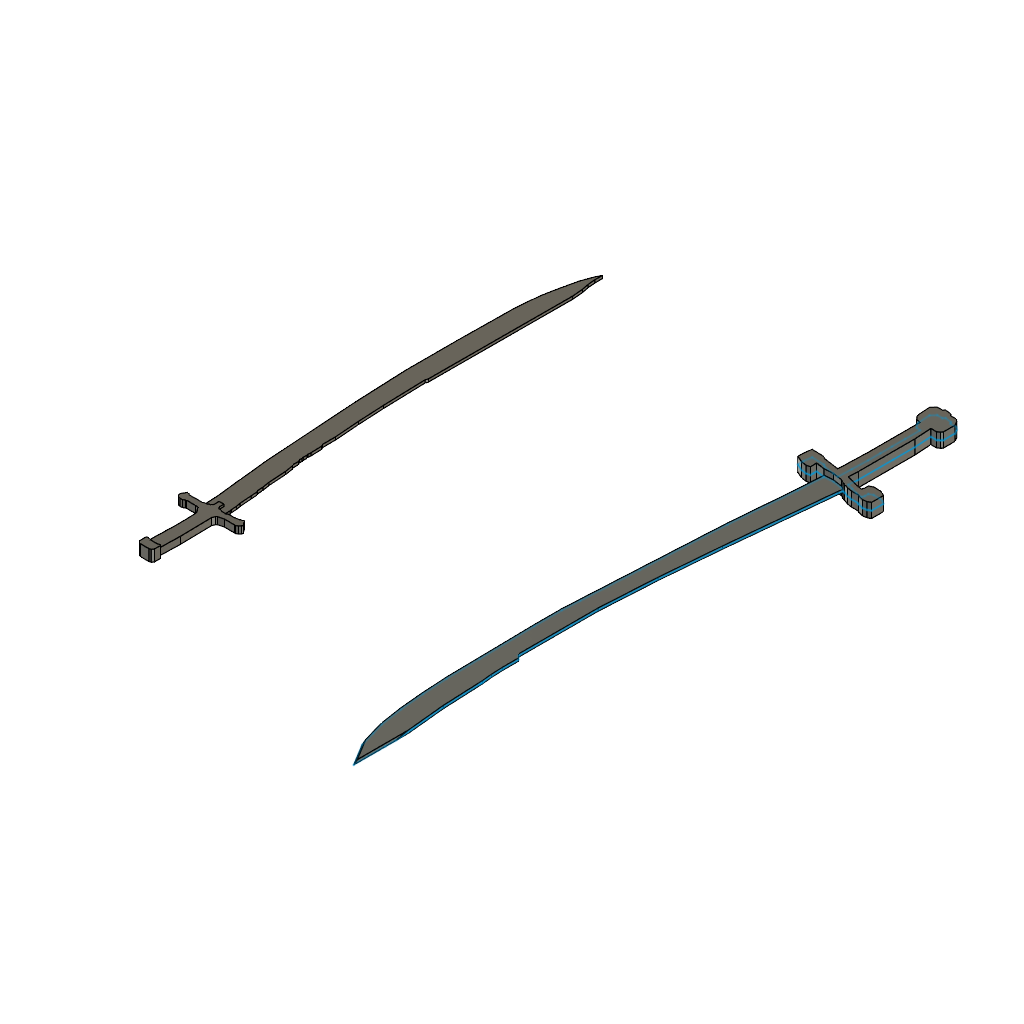
Hungarian_Saber_and_Early_Ottoman_Kilij (Autodesk Fusion 360 design; units mm, degrees)
part number: 2026-09-20-18-35-14-344
Autodesk Fusion 360 part; units mm, degrees
sketch "Sketch1" plane through (0, 0, 0) normal (0, 0, 1) x (1, 0, 0)
sketch "Sketch2" plane through (0, 0, 0) normal (0, 0, 1) x (1, 0, 0)
sketch "Sketch3" plane through (0, 0, 0) normal (0, 0, 1) x (1, 0, 0)
  line L0 (20.535, 40.8255) -> (20.535, 39.7757)
  line L1 (20.535, 39.7757) -> (20.535, 38.8297)
  line L2 (20.535, 38.8297) -> (20.535, 38)
  line L3 (20.535, 38) -> (20.535, 37.125)
  line L4 (20.535, 37.125) -> (20.5, 36)
  line L5 (20.5, 36) -> (20.4699, 35.0318)
  line L6 (20.535, 40.8255) -> (20.25, 40.875)
  line L7 (20.25, 40.875) -> (20.059, 41.0864)
  line L8 (20.059, 41.0864) -> (20, 41.25)
  line L9 (20, 41.25) -> (19.9441, 42.0918)
  line L10 (19.9441, 42.0918) -> (20.2027, 42.3838)
  line L11 (20.2027, 42.3838) -> (20.5761, 42.3838)
  line L12 (21.2093, 42.3262) -> (21.625, 42.3262)
  line L13 (21.625, 42.3262) -> (21.7909, 42.195)
  line L14 (21.7909, 42.195) -> (21.9608, 41.8938)
  line L15 (21.9608, 41.8938) -> (21.9608, 41.0647)
  line L16 (21.9608, 41.0647) -> (21.8758, 40.9573)
  line L17 (21.8758, 40.9573) -> (21.7103, 40.8321)
  line L18 (21.7103, 40.8321) -> (21.2988, 40.8321)
  line L19 (20.5761, 42.3838) -> (20.6845, 42.5021)
  line L20 (20.6845, 42.5021) -> (21.1318, 42.443)
  line L21 (21.1318, 42.443) -> (21.2093, 42.3262)
  line L22 (21.2988, 40.8321) -> (21.375, 39.625)
  line L23 (21.375, 39.625) -> (21.375, 38.0611)
  line L24 (21.375, 38.0611) -> (21.375, 35.5802)
  line L25 (21.375, 35.5802) -> (21.3369, 34.91)
  line L26 (21.3369, 34.91) -> (21.7185, 34.8114)
  line L27 (21.7185, 34.8114) -> (22.125, 34.6875)
  line L28 (22.125, 34.6875) -> (22.5625, 34.625)
  line L29 (22.5625, 34.625) -> (22.6193, 34.8114)
  line L30 (22.6193, 34.8114) -> (22.6193, 35.0625)
  line L31 (22.6193, 35.0625) -> (22.875, 35.1875)
  line L32 (22.875, 35.1875) -> (23.3125, 35.1875)
  line L33 (23.3125, 35.1875) -> (23.5625, 35.125)
  line L34 (23.5625, 35.125) -> (23.75, 35)
  line L35 (23.75, 35) -> (23.75, 34.1588)
  line L36 (23.75, 34.1588) -> (23.5346, 34.0415)
  line L37 (23.5346, 34.0415) -> (23.25, 34)
  line L38 (23.25, 34) -> (22.8707, 34.1002)
  line L39 (22.8707, 34.1002) -> (22.8641, 34.1456)
  line L40 (22.8641, 34.1456) -> (22.3149, 34.1456)
  line L41 (22.3149, 34.1456) -> (21.9876, 34.199)
  line L42 (21.9876, 34.199) -> (21.6695, 34.3194)
  line L43 (21.6695, 34.3194) -> (21.5277, 34.3425)
  line L44 (20.4699, 35.0318) -> (20.1137, 35.0824)
  line L45 (20.1137, 35.0824) -> (19.3962, 35.1842)
  line L46 (19.3962, 35.1842) -> (19.2212, 35.2941)
  line L47 (19.2212, 35.2941) -> (18.3538, 35.3211)
  line L48 (18.3538, 35.3211) -> (18.276, 34.7731)
  line L49 (18.276, 34.7731) -> (18.276, 34.375)
  line L50 (18.276, 34.375) -> (18.7493, 34.1717)
  line L51 (18.7493, 34.1717) -> (19.1165, 34.1196)
  line L52 (19.1165, 34.1196) -> (19.3695, 34.1717)
  line L53 (19.3695, 34.1717) -> (19.3695, 34.375)
  line L54 (19.3695, 34.375) -> (19.3695, 34.625)
  line L55 (19.3695, 34.625) -> (19.9776, 34.5378)
  line L56 (19.9776, 34.5378) -> (19.9776, 34.4491)
  line L57 (19.9776, 34.4491) -> (19.875, 32.75)
  line L58 (19.875, 32.75) -> (19.4846, 28.1583)
  line L59 (19.4846, 28.1583) -> (19.1588, 22.2317)
  line L60 (19.1588, 22.2317) -> (18.9379, 18.2118)
  line L61 (21.5277, 34.3425) -> (21.4775, 34.0352)
  line L62 (21.4775, 34.0352) -> (21.125, 30.5)
  line L63 (21.125, 30.5) -> (20.9643, 28.8881)
  line L64 (20.9643, 28.8881) -> (20.7301, 26.5399)
  line L65 (20.7301, 26.5399) -> (20.5, 23.875)
  line L66 (20.5, 23.875) -> (20.3652, 22.3135)
  line L67 (20.3652, 22.3135) -> (20.25, 20.375)
  line L68 (20.25, 20.375) -> (20.1261, 18.2898)
  line L69 (20.1261, 18.2898) -> (20.1261, 16.375)
  line L70 (20.1261, 16.375) -> (20.1261, 12.625)
  line L71 (20.1261, 12.625) -> (20.375, 12.375)
  line L72 (20.375, 12.375) -> (20.375, 11.25)
  line L73 (18.9379, 18.2118) -> (18.8692, 16.9629)
  line L74 (18.8692, 16.9629) -> (18.8692, 15)
  line L75 (18.8692, 15) -> (18.9379, 11.0327)
  line L76 (18.9379, 11.0327) -> (18.9793, 8.6387)
  line L77 (18.9793, 8.6387) -> (19.0903, 6.8371)
  line L78 (19.0903, 6.8371) -> (19.25, 5.125)
  line L79 (19.25, 5.125) -> (19.5, 3.5)
  line L80 (19.5, 3.5) -> (19.75, 2.625)
  line L81 (19.75, 2.625) -> (20.06, 1.54)
  line L82 (20.06, 1.54) -> (21, 0)
  line L83 (21, 0) -> (21, 2.25)
  line L84 (21, 2.25) -> (21, 3)
  line L85 (21, 3) -> (20.875, 4.25)
  line L86 (20.875, 4.25) -> (20.7563, 5.4372)
  line L87 (20.7563, 5.4372) -> (20.625, 6.75)
  line L88 (20.625, 6.75) -> (20.5511, 8.3332)
  line L89 (20.5511, 8.3332) -> (20.4873, 9.7001)
  line L90 (20.4873, 9.7001) -> (20.4973, 9.4847)
  line L91 (20.375, 11.25) -> (20.4152, 10.4002)
  line L92 (20.4152, 10.4002) -> (20.4873, 9.7001)
  line L93 (19.9776, 34.5378) -> (20.6065, 34.5814)
  line L94 (20.6065, 34.5814) -> (21.2828, 34.4844)
  line L95 (21.2828, 34.4844) -> (21.5277, 34.3425)
  constraint vertical L0
  constraint parallel L0 L1
  constraint parallel L1 L2
  constraint parallel L2 L3
  constraint parallel L4 L5
  constraint horizontal L11
  constraint horizontal L12
  constraint perpendicular L12 L15
  constraint perpendicular L13 L16
  constraint perpendicular L15 L18
  constraint perpendicular L18 L23
  constraint perpendicular L18 L24
  constraint perpendicular L27 L29
  constraint vertical L30
  constraint horizontal L32
  constraint perpendicular L32 L35
  constraint perpendicular L37 L39
  constraint horizontal L40
  constraint parallel L41 L43
  constraint parallel L44 L45
  constraint perpendicular L5 L47
  constraint perpendicular L44 L48
  constraint vertical L49
  constraint perpendicular L48 L51
  constraint vertical L53
  constraint parallel L53 L54
  constraint vertical L56
  constraint parallel L59 L60
  constraint perpendicular L43 L61
  constraint parallel L62 L63
  constraint parallel L63 L64
  constraint parallel L65 L66
  constraint parallel L67 L68
  constraint vertical L69
  constraint parallel L69 L70
  constraint parallel L70 L72
  constraint parallel L60 L73
  constraint parallel L69 L74
  constraint parallel L75 L76
  constraint parallel L80 L81
  constraint vertical L83
  constraint parallel L83 L84
  constraint parallel L85 L86
  constraint parallel L86 L87
  constraint parallel L88 L89
  constraint coincident L89 L90.end
  constraint parallel L55 L94
extrude "Extrude9" add sketch "Sketch3" along normal mid plane 0.2 contours L56 L57 L58 L59 L60 L61 L62 L63 L64 L65 L66 L67 L68 L69 L70 L71 L72 L73 L74 L75 L76 L77 L78 L79 L80 L81 L82 L83 L84 L85 L86 L87 L88 L89 L90 L91 L92 L93 L94 L95 makes body 1
extrude "Extrude10" add sketch "Sketch3" along normal mid plane 1 separate body contours L0 L1 L2 L3 L4 L5 L6 L7 L8 L9 L10 L11 L12 L13 L14 L15 L16 L17 L18 L19 L20 L21 L22 L23 L24 L25 L26 L27 L28 L29 L30 L31 L32 L33 L34 L35 L36 L37 L38 L39 L40 L41 L42 L43 L44 L45 L46 L47 L48 L49 L50 L51 L52 L53 L54 L55 L93 L94 L95 makes body 2
chamfer "Chamfer5" distance 0.1 angle 45 1 edges at (20.53, 0.77, 0.1) tangent chain off on bodies 1
chamfer "Chamfer6" distance 0.1 angle 45 1 edges at (21, 1.596, 0.1) tangent chain off on bodies 1
chamfer "Chamfer7" distance 0.1 angle 45 1 edges at (20.53, 0.77, -0.1) tangent chain off on bodies 1
chamfer "Chamfer8" distance 0.1 angle 45 1 edges at (21, 1.596, -0.1) tangent chain off on bodies 1
sketch "Sketch4" plane through (0, 0, 0) normal (0, 0, 1) x (1, 0, 0)
sketch "Sketch5" plane through (0, 0, 0) normal (0, 0, 1) x (1, 0, 0)
  line L0 (0.9998, 10.1385) -> (0.9211, 9.9479)
  line L1 (0.9211, 9.9479) -> (0.9412, 8.882)
  line L2 (0.9412, 8.882) -> (0.964, 7.6796)
  line L3 (0.964, 7.6796) -> (0.9526, 7.2039)
  line L4 (0.9526, 7.2039) -> (0.9314, 6.3174)
  line L5 (0.9314, 6.3174) -> (0.7833, 6.2509)
  line L6 (0.7833, 6.2509) -> (0.5428, 6.2464)
  line L7 (0.5428, 6.2464) -> (0.2434, 6.2509)
  line L8 (0.2434, 6.2509) -> (0.0858, 6.3049)
  line L9 (0.0858, 6.3049) -> (0.07, 6.34)
  line L10 (0.07, 6.34) -> (0.1, 7.5)
  line L11 (0.1, 7.5) -> (0.118, 8.2452)
  line L12 (0.118, 8.2452) -> (0.1, 7.5)
  line L13 (0.118, 8.2452) -> (0.109, 8.9555)
  line L14 (0.109, 8.9555) -> (0.0862, 9.6131)
  line L15 (0.0862, 9.6131) -> (0.0385, 9.7795)
  line L16 (0.0385, 9.7795) -> (-0.05, 9.9)
  line L17 (-0.05, 9.9) -> (-0.1552, 10.0432)
  line L18 (-0.1552, 10.0432) -> (-0.1742, 10.1095)
  line L19 (-0.1742, 10.1095) -> (-0.3662, 10.1243)
  line L20 (-0.3662, 10.1243) -> (-0.4152, 10.128)
  line L21 (-0.4152, 10.128) -> (-1.0257, 10.1243)
  line L22 (-1.0257, 10.1243) -> (-0.4152, 10.128)
  line L23 (-1.0257, 10.1243) -> (-1.1064, 10.1012)
  line L24 (-1.1064, 10.1012) -> (-1.2276, 10.019)
  line L25 (-1.2276, 10.019) -> (-1.4058, 10.0179)
  line L26 (-1.4058, 10.0179) -> (-1.5371, 10.0484)
  line L27 (-1.5371, 10.0484) -> (-1.6602, 10.1906)
  line L28 (-1.6602, 10.1906) -> (-1.6895, 10.3049)
  line L29 (-1.6895, 10.3049) -> (-1.6602, 10.3698)
  line L30 (-1.6602, 10.3698) -> (-1.6513, 10.3896)
  line L31 (-1.6513, 10.3896) -> (-1.6181, 10.4631)
  line L32 (-1.6181, 10.4631) -> (-1.5768, 10.4846)
  line L33 (-1.5768, 10.4846) -> (-1.56, 10.54)
  line L34 (-1.56, 10.54) -> (-1.56, 10.58)
  line L35 (-1.56, 10.58) -> (-1.54, 10.61)
  line L36 (-1.54, 10.61) -> (-1.5186, 10.6444)
  line L37 (-1.5186, 10.6444) -> (-1.4309, 10.6444)
  line L38 (-1.4309, 10.6444) -> (-1.3487, 10.6195)
  line L39 (-1.3487, 10.6195) -> (-1.3, 10.57)
  line L40 (-1.3, 10.57) -> (-1.2734, 10.562)
  line L41 (-1.2734, 10.562) -> (-0.3379, 10.57)
  line L42 (-0.3379, 10.57) -> (-0.2951, 10.6121)
  line L43 (-0.2951, 10.6121) -> (-0.0594, 10.6395)
  line L44 (0.9998, 10.1385) -> (1.0753, 10.2152)
  line L45 (1.0753, 10.2152) -> (1.4, 10.3)
  line L46 (1.4, 10.3) -> (1.4603, 10.3158)
  line L47 (1.4603, 10.3158) -> (1.9, 10.3158)
  line L48 (1.9, 10.3158) -> (2.1, 10.3158)
  line L49 (2.1, 10.3158) -> (2.2, 10.3158)
  line L50 (2.2, 10.3158) -> (2.2647, 10.3079)
  line L51 (2.2647, 10.3079) -> (2.3879, 10.3893)
  line L52 (2.3879, 10.3893) -> (2.5, 10.5)
  line L53 (2.5, 10.5) -> (2.5461, 10.6141)
  line L54 (2.5461, 10.6141) -> (2.444, 10.7175)
  line L55 (2.444, 10.7175) -> (2.3731, 10.8046)
  line L56 (2.3731, 10.8046) -> (2.35, 10.85)
  line L57 (2.35, 10.85) -> (2.3414, 10.8862)
  line L58 (2.3414, 10.8862) -> (2.3171, 10.9146)
  line L59 (2.3171, 10.9146) -> (2.28, 10.93)
  line L60 (2.28, 10.93) -> (2.2251, 10.9223)
  line L61 (2.2251, 10.9223) -> (2.2058, 10.9004)
  line L62 (2.2058, 10.9004) -> (2.1809, 10.8722)
  line L63 (2.1809, 10.8722) -> (2.1558, 10.8686)
  line L64 (2.1558, 10.8686) -> (2.1163, 10.8631)
  line L65 (2.1163, 10.8631) -> (2.08, 10.8631)
  line L66 (2.08, 10.8631) -> (2.06, 10.85)
  line L67 (2.06, 10.85) -> (2.05, 10.83)
  line L68 (2.05, 10.83) -> (2.04, 10.81)
  line L69 (2.04, 10.81) -> (1.9855, 10.81)
  line L70 (1.9855, 10.81) -> (1.936, 10.81)
  line L71 (1.936, 10.81) -> (1.88, 10.8)
  line L72 (1.88, 10.8) -> (1.82, 10.8)
  line L73 (1.82, 10.8) -> (1.7858, 10.7832)
  line L74 (1.7858, 10.7832) -> (1.7402, 10.7607)
  line L75 (1.7402, 10.7607) -> (1.4783, 10.7607)
  line L76 (1.4783, 10.7607) -> (1.364, 10.7607)
  line L77 (1.364, 10.7607) -> (1.28, 10.74)
  line L78 (1.28, 10.74) -> (1.25, 10.71)
  line L79 (1.25, 10.71) -> (1.22, 10.69)
  line L80 (1.22, 10.69) -> (1.1339, 10.69)
  line L81 (1.1339, 10.69) -> (1.02, 10.69)
  line L82 (1.02, 10.69) -> (0.91, 10.7)
  line L83 (0.91, 10.7) -> (0.86, 10.73)
  line L84 (0.86, 10.73) -> (0.82, 10.76)
  line L85 (0.82, 10.76) -> (0.7495, 10.7664)
  line L86 (0.7495, 10.7664) -> (0.82, 10.76)
  line L87 (0.65, 10.76) -> (0.5811, 10.8117)
  line L88 (0.5811, 10.8117) -> (0.53, 10.88)
  line L89 (0.65, 10.76) -> (0.7495, 10.7664)
  line L90 (-0.0594, 10.6395) -> (0, 10.7)
  line L91 (0, 10.7) -> (0.1019, 10.7119)
  line L92 (0.1019, 10.7119) -> (0.15, 10.8)
  line L93 (0.15, 10.8) -> (0.1912, 10.8419)
  line L94 (0.1912, 10.8419) -> (0.1912, 11.0201)
  line L95 (0.1912, 11.0201) -> (0.1912, 11.2204)
  line L96 (0.1912, 11.2204) -> (0.53, 11.2204)
  line L97 (0.53, 11.2204) -> (0.53, 10.88)
  line L98 (0.9314, 6.3174) -> (0.9739, 6.2635)
  line L99 (0.9739, 6.2635) -> (0.9739, 5.828)
  line L100 (0.9739, 5.828) -> (0.8774, 5.6877)
  line L101 (0.8774, 5.6877) -> (0.7541, 5.6494)
  line L102 (0.7541, 5.6494) -> (0.1674, 5.6494)
  line L103 (0.1674, 5.6494) -> (0.0101, 5.7196)
  line L104 (0.0101, 5.7196) -> (-0.075, 5.828)
  line L105 (-0.075, 5.828) -> (-0.075, 6.2659)
  line L106 (-0.075, 6.2659) -> (-0.0325, 6.3082)
  line L107 (-0.0325, 6.3082) -> (0.03, 6.33)
  line L108 (0.03, 6.33) -> (0.07, 6.34)
  line L109 (-0.2951, 10.6121) -> (-0.3632, 11.7311)
  line L110 (-0.3632, 11.7311) -> (-0.5655, 13.4701)
  line L111 (-0.5655, 13.4701) -> (-0.572, 13.5768)
  line L112 (-0.572, 13.5768) -> (-0.6579, 14.4362)
  line L113 (-0.6579, 14.4362) -> (-0.7776, 15.4651)
  line L114 (-0.7776, 15.4651) -> (-0.8555, 16.6133)
  line L115 (-0.8555, 16.6133) -> (-0.9663, 18.2476)
  line L116 (-0.9663, 18.2476) -> (-1.164, 21.1632)
  line L117 (-1.164, 21.1632) -> (-1.2452, 22.3594)
  line L118 (-1.2452, 22.3594) -> (-1.3, 23.6)
  line L119 (-1.3, 23.6) -> (-1.3553, 24.8509)
  line L120 (-1.3553, 24.8509) -> (-1.4131, 26.1577)
  line L121 (-1.4131, 26.1577) -> (-1.4131, 27.7)
  line L122 (-1.4131, 27.7) -> (-1.4131, 29.8863)
  line L123 (-1.4131, 29.8863) -> (-1.3842, 32.1188)
  line L124 (-1.3842, 32.1188) -> (-1.363, 33.7541)
  line L125 (-1.363, 33.7541) -> (-1.3, 34.65)
  line L126 (-1.3, 34.65) -> (-1.1996, 35.549)
  line L127 (-1.1996, 35.549) -> (-1.0312, 36.4509)
  line L128 (-1.0312, 36.4509) -> (-0.7364, 37.7837)
  line L129 (-0.7364, 37.7837) -> (-0.4272, 38.6431)
  line L130 (-0.4272, 38.6431) -> (-0.2481, 38.9641)
  line L131 (-0.2481, 38.9641) -> (-0.2481, 38.4346)
  line L132 (-0.2481, 38.4346) -> (-0.2, 37.9)
  line L133 (-0.2, 37.9) -> (-0.1, 37.4)
  line L134 (-0.1, 37.4) -> (-0.0324, 36.6479)
  line L135 (-0.0324, 36.6479) -> (-0.0662, 26.3744)
  line L136 (-0.0662, 26.3744) -> (-0.1246, 26.212)
  line L137 (-0.1246, 26.212) -> (-0.0322, 23.1576)
  line L138 (-0.0322, 23.1576) -> (0.0658, 21.2837)
  line L139 (0.0658, 21.2837) -> (0.1843, 19.739)
  line L140 (0.1843, 19.739) -> (0.2015, 19.515)
  line L141 (0.2015, 19.515) -> (0.2079, 18.5656)
  line L142 (0.2079, 18.5656) -> (0.2843, 18.4354)
  line L143 (0.2843, 18.4354) -> (0.3081, 17.6479)
  line L144 (0.3081, 17.6479) -> (0.2962, 17.4446)
  line L145 (0.2962, 17.4446) -> (0.317, 17.3548)
  line L146 (0.317, 17.3548) -> (0.3081, 17.093)
  line L147 (0.3081, 17.093) -> (0.3341, 16.981)
  line L148 (0.3341, 16.981) -> (0.3277, 16.7926)
  line L149 (0.3277, 16.7926) -> (0.4047, 16.6756)
  line L150 (0.4047, 16.6756) -> (0.4047, 16.25)
  line L151 (0.4047, 16.25) -> (0.4611, 16.1645)
  line L152 (0.4611, 16.1645) -> (0.5167, 15.8253)
  line L153 (0.5167, 15.8253) -> (0.5526, 15.607)
  line L154 (0.5526, 15.607) -> (0.6, 14.9)
  line L155 (0.6, 14.9) -> (0.6393, 14.3148)
  line L156 (0.6393, 14.3148) -> (0.7228, 13.8059)
  line L157 (0.7228, 13.8059) -> (0.75, 13.4)
  line L158 (0.75, 13.4) -> (0.8033, 13.3152)
  line L159 (0.8033, 13.3152) -> (0.8341, 12.8581)
  line L160 (0.8341, 12.8581) -> (0.9, 12)
  line L161 (0.9, 12) -> (0.9555, 11.7114)
  line L162 (0.9555, 11.7114) -> (0.9863, 11.3105)
  line L163 (0.9863, 11.3105) -> (1.0109, 11.1826)
  line L164 (1.0109, 11.1826) -> (1.0227, 10.8366)
  line L165 (1.0227, 10.8366) -> (1.02, 10.69)
  constraint parallel L1 L2
  constraint parallel L3 L4
  constraint perpendicular L2 L6
  constraint perpendicular L5 L9
  constraint parallel L11 L12
  constraint parallel L16 L17
  constraint parallel L15 L18
  constraint parallel L19 L20
  constraint parallel L21 L22
  constraint perpendicular L18 L23
  constraint parallel L22 L25
  constraint parallel L30 L31
  constraint vertical L34
  constraint perpendicular L34 L37
  constraint perpendicular L33 L38
  constraint parallel L38 L40
  constraint perpendicular L39 L42
  constraint parallel L45 L46
  constraint horizontal L47
  constraint parallel L47 L48
  constraint parallel L48 L49
  constraint perpendicular L52 L54
  constraint parallel L61 L62
  constraint parallel L60 L63
  constraint parallel L60 L64
  constraint horizontal L65
  constraint parallel L67 L68
  constraint parallel L65 L69
  constraint parallel L69 L70
  constraint parallel L69 L72
  constraint parallel L73 L74
  constraint parallel L72 L75
  constraint parallel L75 L76
  constraint parallel L76 L80
  constraint parallel L80 L81
  constraint parallel L82 L85
  constraint parallel L85 L86
  constraint parallel L84 L87
  constraint parallel L43 L91
  constraint parallel L90 L93
  constraint vertical L94
  constraint parallel L94 L95
  constraint perpendicular L94 L96
  constraint perpendicular L96 L97
  constraint vertical L99
  constraint perpendicular L99 L102
  constraint perpendicular L102 L105
  constraint perpendicular L43 L110
  constraint parallel L109 L111
  constraint parallel L110 L113
  constraint parallel L114 L115
  constraint parallel L115 L116
  constraint parallel L116 L117
  constraint parallel L118 L119
  constraint parallel L119 L120
  constraint vertical L121
  constraint parallel L121 L122
  constraint parallel L123 L124
  constraint vertical L131
  constraint parallel L132 L134
  constraint parallel L129 L136
  constraint parallel L139 L140
  constraint parallel L137 L143
  constraint parallel L145 L147
  constraint parallel L146 L148
  constraint vertical L150
  constraint parallel L149 L151
  constraint parallel L152 L153
  constraint parallel L154 L155
  constraint parallel L153 L156
  constraint parallel L155 L157
  constraint parallel L160 L162
  constraint parallel L161 L163
extrude "Extrude11" add sketch "Sketch5" along normal mid plane 0.2 separate body contours L43 L82 L83 L84 L85 L86 L87 L88 L89 L90 L91 L92 L93 L94 L95 L96 L97 L109 L110 L111 L112 L113 L114 L115 L116 L117 L118 L119 L120 L121 L122 L123 L124 L125 L126 L127 L128 L129 L130 L131 L132 L133 L134 L135 L136 L137 L138 L139 L140 L141 L142 L143 L144 L145 L146 L147 L148 L149 L150 L151 L152 L153 L154 L155 L156 L157 L158 L159 L160 L161 L162 L163 L164 L165 makes body 3
extrude "Extrude12" add sketch "Sketch5" along normal mid plane 0.5 contours L0 L1 L2 L3 L4 L5 L6 L7 L8 L9 L10 L11 L12 L13 L14 L15 L16 L17 L18 L19 L20 L21 L22 L23 L24 L25 L26 L27 L28 L29 L30 L31 L32 L33 L34 L35 L36 L37 L38 L39 L40 L41 L42 L43 L44 L45 L46 L47 L48 L49 L50 L51 L52 L53 L54 L55 L56 L57 L58 L59 L60 L61 L62 L63 L64 L65 L66 L67 L68 L69 L70 L71 L72 L73 L74 L75 L76 L77 L78 L79 L80 L81 L82 L83 L84 L85 L86 L87 L88 L89 L90 L91 L92 L93 L94 L95 L96 L97 bodies 3
extrude "Extrude13" add sketch "Sketch5" along normal mid plane 0.8 contours L5 L6 L7 L8 L9 L98 L99 L100 L101 L102 L103 L104 L105 L106 L107 L108 bodies 3
sketch "Sketch19" plane through (0, 0, 0) normal (0, 0, 1) x (1, 0, 0)
sketch "Sketch20" plane through (0, 0, 0) normal (0, 1, 0) x (1, 0, 0)
  line L0 (-2.2, 0) -> (-3.6, 0)
  circle A0 centre (-2.9, 0) radius 0.7
  constraint midpoint L0 A0.centre
  constraint coincident L0.end A0
sketch "Sketch21" plane through (0, 0, 0) normal (0, 0, 1) x (1, 0, 0)
  line L0 (-3.9, 1.65) -> (-1.8, 1.65)
  line L1 (-1.8, 1.65) -> (-1.8, 0)
  line L2 (-1.8, 0) -> (-3.9, 0)
  line L3 (-3.9, 0) -> (-3.9, 1.65)
  constraint horizontal L0
  constraint vertical L1
  constraint horizontal L2
  constraint vertical L3
sketch "Sketch22" plane through (-1.8, 0, 0) normal (1, 0, 0) x (0, 1, 0)
sketch "Sketch23" plane through (0, 0, 0) normal (0, 0, 1) x (1, 0, 0)
  line L0 (-1.8, 0) -> (-1.7181, -0.0839)
  line L1 (-1.7181, -0.0839) -> (3.1, -0.0839)
  arc A0 (3.1, -0.0839) -> (-1.8, 1.4) centre (-2.8014, -10.7391) ccw
  constraint horizontal L1
sketch "Sketch6" plane through (0, 0, 0) normal (0, 0, 1) x (1, 0, 0)
sketch "Sketch7" plane through (0, 0, 0) normal (0, 1, 0) x (1, 0, 0)
  circle A0 centre (-47.8521, 0.0052) radius 0.6521
extrude "Extrude14" [suppressed]
sketch "Sketch8" plane through (0, 0, 0) normal (1, 0, 0) x (0, 1, 0)
sketch "Sketch18" plane through (0, 0, 0) normal (0, 0, 1) x (1, 0, 0)
sketch "Sketch9" plane through (0, 0, 0) normal (0, 0, 1) x (1, 0, 0)
  line L0 (-47, -15) -> (-48.8698, -15)
  line L1 (-48.8698, -15) -> (-48.8698, -16.6523)
  line L2 (-48.8698, -16.6523) -> (-47, -16.6523)
  line L3 (-47, -16.6523) -> (-47, -15)
  constraint horizontal L0
  constraint vertical L1
  constraint horizontal L2
  constraint vertical L3
moveface "MoveFace1" [suppressed]
moveface "MoveFace2" [suppressed]
moveface "MoveFace3" [suppressed]
moveface "MoveFace4" [suppressed]
extrude "Extrude15" [suppressed]
sketch "Sketch10" plane through (-47, 0, 0) normal (1, 0, 0) x (0, 1, 0)
  line L0 (-15, -0.7) -> (-15, 0.7)
  line L1 (-15, 0.7) -> (-16.6523, 0.7)
  line L2 (-16.6523, 0.7) -> (-16.6523, -0.7)
  line L3 (-16.6523, -0.7) -> (-15, -0.7)
  line L4 (-15.05, -0.65) -> (-15.05, 0.65)
  line L5 (-15.05, 0.65) -> (-16.6, 0.65)
  line L6 (-16.6, 0.65) -> (-16.6, -0.65)
  line L7 (-16.6, -0.65) -> (-15.05, -0.65)
  constraint perpendicular L1 L4
  constraint perpendicular L4 L5
  constraint perpendicular L1 L6
extrude "Extrude16" [suppressed]
move_body "Move1" [suppressed]
move_body "Move2" [suppressed]
delete_face "DeleteFace2" [suppressed]
extrude "Extrude17" [suppressed]
extrude "Extrude18" [suppressed]
delete_face "DeleteFace1" [suppressed]
sketch "Sketch11" plane through (0, 0, 0) normal (0, 1, 0) x (1, 0, 0)
sketch "Sketch17" plane through (-47, 0, 0) normal (1, 0, 0) x (0, 1, 0)
  line L0 (-16.6623, -0.7) -> (-14.91, -0.7)
  line L1 (-14.91, -0.7) -> (-14.91, 0.7)
  line L2 (-14.91, 0.7) -> (-16.6623, 0.7)
  line L3 (-16.6623, 0.7) -> (-16.6623, -0.7)
fillet "Fillet20" [suppressed]
fillet "Fillet21" [suppressed]
fillet "Fillet22" [suppressed]
